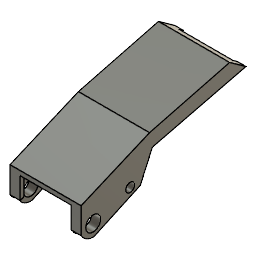
full-extinguisher-assembly (Autodesk Fusion 360 archive; units mm, degrees)
design "triggertop"
Autodesk Fusion 360 part; units mm, degrees
sketch "Sketch1" plane through (0, 0, 0) normal (1, 0, 0) x (0, 1, 0)
  line L0 (-0.0636, 2.4163) -> (-0.0636, 11.2)
  arc A0 (-0.0636, 2.4163) -> (4.2508, 0) centre (4.0754, 4.7468) ccw
  line L1 (1.75, 0) -> (22.5, 0)
  line L2 (4.2508, 0) -> (19.8905, 7.1582)
  line L3 (19.8905, 7.1582) -> (23.973, 16.2869)
  line L4 (23.973, 16.2869) -> (55.5289, 24.0634)
  line L5 (-0.0636, 11.2) -> (23, 21)
  line L6 (23, 21) -> (50, 28)
  line L7 (50, 28) -> (55.5289, 24.0634)
  line L8 (49.7397, 26.5895) -> (52.4669, 24.6477)
  line L9 (23.0455, 17.3972) -> (52.4669, 24.6477)
  line L10 (18.9038, 8.1363) -> (23.0455, 17.3972)
  line L11 (3.9643, 1.2986) -> (18.9038, 8.1363)
  arc A1 (1.2364, 2.7865) -> (3.9643, 1.2986) centre (4.0754, 4.7468) ccw
  line L12 (1.2364, 2.7865) -> (1.2364, 10.3399)
  line L13 (1.2364, 10.3399) -> (23.4196, 19.7658)
  line L14 (23.4196, 19.7658) -> (49.7397, 26.5895)
  line L15 (1.2364, 10.3399) -> (-0.0636, 9.7875)
  line L16 (1.2364, 2.7865) -> (-0.0636, 2.4163)
  line L17 (49.7397, 26.5895) -> (51.3827, 27.0155)
  line L18 (52.4669, 24.6477) -> (54.11, 25.0737)
  dimension "d2" = 4.75
  dimension "d3" = 11.2
  dimension "d4" = 17.2
  dimension "d5" = 10
  dimension "d6" = 32.5
  dimension "d10" = -1.3
  constraint vertical L0
  constraint coincident A0.end L1
  constraint coincident L0 L15.end
  constraint parallel L13 L15
  constraint coincident L7 L17.end
  constraint parallel L14 L17
  constraint coincident L7 L18.end
  constraint parallel L17 L18
  measures "d2" radius of A0
  measures "d3" vertical distance of origin L0.end
  measures "d4" distance of A0.end L2.end
  measures "d5" distance of L2.end L3.end
  measures "d6" distance of L3.end L4.end
extrude "Extrude1" add sketch "Sketch1" along normal mid plane 24
extrude "Extrude4" cut sketch "Sketch1" along normal mid plane 18 contours A0 L2 L3 L4 L7 L9 L10 L11 A1 L16 L18 | L8 L9 L10 L11 A1 L12 L13 L14
sketch "Sketch2" plane through (0, -0.0636, 0) normal (0, -1, 0) x (1, 0, 0)
  line L0 (9, 2.4163) -> (12, 2.4163)
  line L1 (12, 2.4163) -> (12, 11.2)
  line L2 (12, 11.2) -> (-12, 11.2)
  line L3 (-12, 11.2) -> (-12, 2.4163)
  line L4 (-12, 2.4163) -> (-9, 2.4163)
  line L5 (-9, 2.4163) -> (9, 2.4163)
  line L6 (-8.6058, 9.6823) -> (-8.6058, 2.4163)
  line L7 (-8.6058, 2.4163) -> (-10.5, 2.4163)
  line L8 (0, 2.4163) -> (0, 11.2)
  line L9 (8.6058, 9.6823) -> (8.6058, 2.4163)
  line L10 (8.6058, 2.4163) -> (10.5, 2.4163)
  line L11 (-8.6058, 9.6823) -> (8.6058, 9.6823)
  line L12 (8.6058, 2.4163) -> (-8.6058, 2.4163)
  constraint midpoint L4 L7.end
  constraint coincident L5 L6.end
  constraint perpendicular L5 L6
  constraint symmetric L7.end L8 L10.end
  constraint symmetric L6.start L8 L9.start
  constraint symmetric L6.end L8 L9.end
extrude "Extrude5" cut sketch "Sketch2" against normal blind 22.5 contours L5 L8 L9 L11 L12 | L5 L6 L8 L11 L12
sketch "Sketch3" plane through (12, 0, 0) normal (1, 0, 0) x (0, 1, 0)
  line L0 (19.8905, 7.1582) -> (23.973, 16.2869)
  line L1 (23.973, 16.2869) -> (55.5289, 24.0634)
  line L2 (55.5289, 24.0634) -> (50, 28)
  line L3 (50, 28) -> (23, 21)
  line L4 (23, 21) -> (-0.0636, 11.2)
  circle A0 centre (4, 4) radius 2.5
  arc A1 (-0.0636, 2.4163) -> (3.9, 0) centre (4.0754, 4.7468) ccw
  line L5 (3.9, 0) -> (4.2508, 0)
  line L6 (4.2508, 0) -> (19.8905, 7.1582)
  line L7 (-0.0636, 11.2) -> (-0.0636, 2.4163)
  dimension "d19" = 5
  measures "d19" diameter of A0
extrude "Extrude6" cut sketch "Sketch3" against normal blind 31 contours A0
sketch "Sketch5" plane through (12, 0, 0) normal (1, 0, 0) x (0, 1, 0)
  circle A0 centre (4, 4) radius 2.5
  arc A1 (-0.0636, 2.4163) -> (3.9, 0) centre (4.0754, 4.7468) ccw
  line L0 (3.9, 0) -> (4.2508, 0)
  line L1 (4.2508, 0) -> (19.8905, 7.1582)
  line L2 (19.8905, 7.1582) -> (23.973, 16.2869)
  line L3 (23.973, 16.2869) -> (55.5289, 24.0634)
  line L4 (55.5289, 24.0634) -> (50, 28)
  line L5 (50, 28) -> (23, 21)
  line L6 (23, 21) -> (-0.0636, 11.2)
  line L7 (-0.0636, 11.2) -> (-0.0636, 2.4163)
  line L8 (4, 4) -> (16.4795, 8.2844) construction
  circle A2 centre (16.4795, 8.2844) radius 1.5
  line L9 (16.4795, 8.2844) -> (17.4964, 6.0625) construction
  dimension "d28" = 3
  dimension "d31" = 3
  constraint coincident A0.centre L8.start
  constraint coincident L8.end A2.centre
  constraint coincident L1 L9.end
  constraint perpendicular L1 L9
  measures "d28" diameter of A2
extrude "Extrude8" cut sketch "Sketch5" against normal blind 34 contours A2

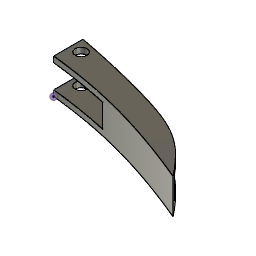
design "bottom trigger"
Autodesk Fusion 360 part; units mm, degrees
derive "DerivedContext1" from "assembly trigger v6"
sketch "Sketch1" plane through (0, 0, 0) normal (0, 0, 1) x (1, 0, 0)
  line L0 (70, 0) -> (0, 0) construction
  line L1 (0, 0) -> (0, 19) construction
  line L2 (0, 19) -> (0, 31.5)
  spline S0 degree 5 poles (0, 19) (3.7774, 18.5857) (11.047, 17.6563) (21.0963, 15.9597) (33.0212, 13.1761) (46.292, 9.1181) (56.1059, 5.5879) (63.1632, 2.8329) (67.7421, 0.9517) (70, 0) knots 0 0 0 0 0 0 0.2 0.4 0.6 0.8 1 1 1 1 1 1
  line L3 (-9.5744, 20.05) -> (9.5744, 17.95)
  spline S1 degree 5 poles (0, 31.5) (1.2479, 31.2649) (3.7995, 30.7712) (7.7943, 29.9605) (13.4574, 28.7383) (21.0918, 26.9563) (29.128, 24.9178) (37.3244, 22.5914) (44.9227, 20.0618) (51.5658, 17.1401) (57.585, 13.3042) (62.3122, 9.0275) (66.0506, 4.9007) (68.6634, 1.7073) (70, 0) knots 0 0 0 0 0 0 0.1 0.2 0.3 0.4 0.5 0.6 0.7 0.8 0.9 1 1 1 1 1 1
  line L4 (62.9488, 9.0069) -> (77.0512, -9.0069)
  line L5 (27.798, 25.3994) -> (45.0092, 20.1534)
  line L6 (0, 19) -> (0, 22)
  spline S2 degree 5 poles (-0.0005, 21.9997) (3.6175, 21.6029) (10.5796, 20.7113) (20.2024, 19.0799) (31.6183, 16.3979) (44.3187, 12.4831) (53.7089, 9.0754) (60.4606, 6.4154) (64.8409, 4.5988) (67.0008, 3.6796) knots 0 0 0 0 0 0 0.2 0.4 0.6 0.8 1 1 1 1 1 1
  line L7 (-9.5749, 23.0497) -> (9.5739, 20.9497)
  line L8 (25, 17.8107) -> (25, 14.896)
  point P0 (36.4036, 22.7764)
  dimension "d1" = 70
  dimension "d3" = 19
  dimension "d4" = 12.5
  dimension "d16" = 3
  dimension "d19" = 25
  constraint horizontal L0
  constraint coincident L0.end L1.start
  constraint perpendicular L0 L1
  constraint midpoint L1.end L3
  constraint midpoint L0.start L4
  constraint midpoint P0 L5
  constraint parallel L2 L6
  constraint midpoint S2.start L7
  constraint coincident S1 S2.end
  constraint coincident S2 L8.start
  constraint coincident S0 L8.end
  constraint parallel L2 L8
  measures "d1" distance of L0.start L0.end
  measures "d3" distance of L0.end L1.end
  measures "d4" distance of L1.end L2.end
  measures "d16" distance of L1.end L6.end
  measures "d19" distance of L6 L8
extrude "Extrude1" add sketch "Sketch1" along normal mid plane 15
extrude "Extrude3" cut sketch "Sketch1" along normal mid plane 10 contours L2 S0 L6 S2 L8 | L2 S1 S2
sketch "Sketch8" plane through (0, 0, 0) normal (-1, 0, 0) x (0, -1, 0)
  line L0 (-31.5, 5) -> (-19, 5)
  line L1 (-19, -5) -> (-31.5, -5)
  line L2 (-31.5, -5) -> (-31.5, -7.5)
  line L3 (-31.5, -7.5) -> (-19, -7.5)
  line L4 (-19, 5) -> (-19, 7.5)
  line L5 (-19, 7.5) -> (-31.5, 7.5)
  line L6 (-31.5, 7.5) -> (-31.5, 5)
  line L7 (-19, -7.5) -> (-19, -5)
sketch "Sketch10" plane through (0, 0, 7.5) normal (0, 0, 1) x (-1, 0, 0)
  spline S0 degree 5 poles (0, -19) (-3.7774, -18.5857) (-11.047, -17.6563) (-21.0963, -15.9597) (-33.0212, -13.1761) (-46.292, -9.1181) (-56.1059, -5.5879) (-63.1632, -2.8329) (-67.7421, -0.9517) (-70, 0) knots 0 0 0 0 0 0 0.2 0.4 0.6 0.8 1 1 1 1 1 1
  spline S1 degree 5 poles (-70, 0) (-68.6634, -1.7073) (-66.0506, -4.9007) (-62.3122, -9.0275) (-57.585, -13.3042) (-51.5658, -17.1401) (-44.9227, -20.0618) (-37.3244, -22.5914) (-29.128, -24.9178) (-21.0918, -26.9563) (-13.4574, -28.7383) (-7.7943, -29.9605) (-3.7995, -30.7712) (-1.2479, -31.2649) (0, -31.5) knots -1 -1 -1 -1 -1 -1 -0.9 -0.8 -0.7 -0.6 -0.5 -0.4 -0.3 -0.2 -0.1 0 0 0 0 0 0
  line L0 (0, -31.5) -> (0, -19)
  circle A0 centre (-4.3353, -26.3526) radius 2.5
  dimension "d23" = 5
  measures "d23" diameter of A0
extrude "Extrude5" cut sketch "Sketch10" against normal blind 16 contours A0
